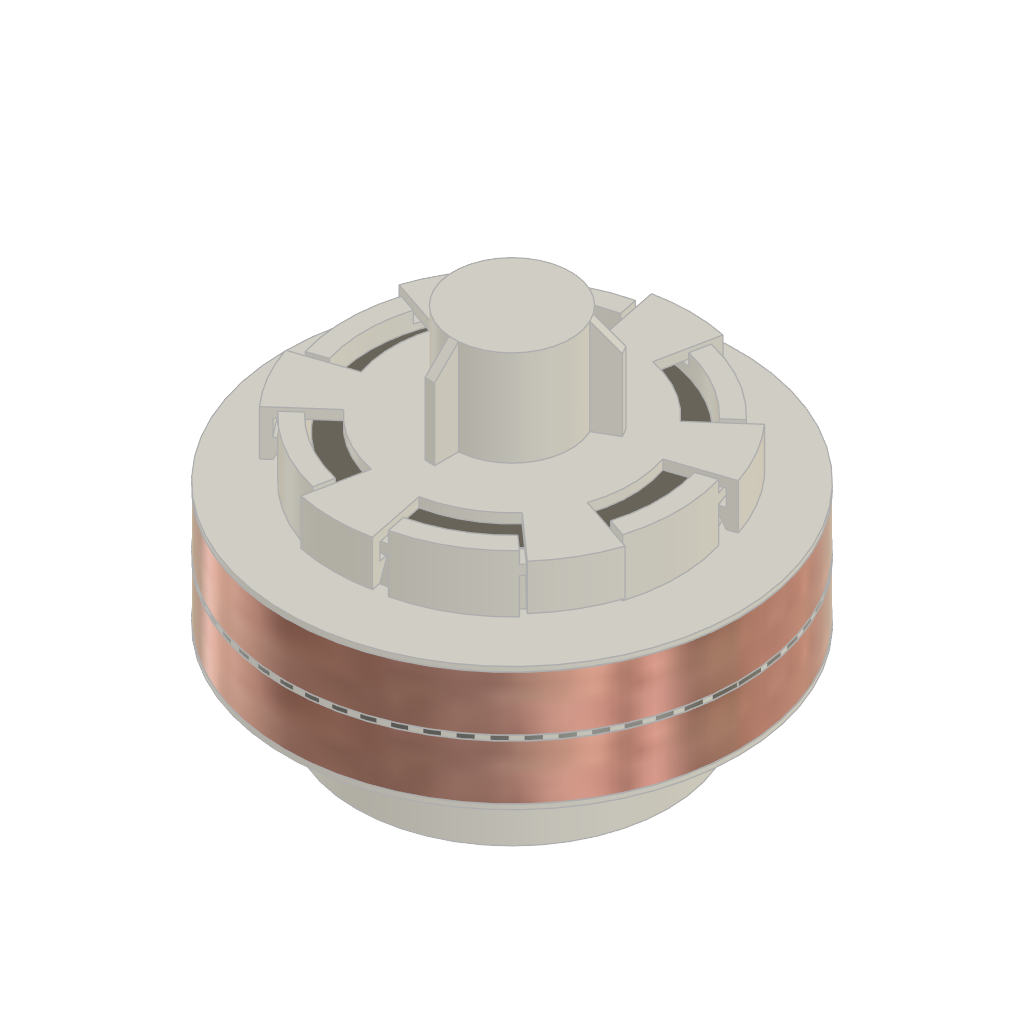
vcm_switch_v01 (Autodesk Fusion 360 design; units mm, degrees)
part number: 2026-10-25-15-28-20-150
part number: 2026-10-28-20-44-21-874
part number: 2026-10-28-20-48-56-404
Autodesk Fusion 360 part; units mm, degrees
sketch "Sketch1" plane through (0, 0, 0) normal (0, 1, 0) x (1, 0, 0)
  line L0 (2, -1.9) -> (2, -2.9)
  line L1 (2, -2.9) -> (5.95, -2.9)
  line L2 (5.95, -2.9) -> (5.95, 0)
  line L3 (5.95, 0) -> (3.9, 0)
  line L4 (1.85, -3.55) -> (1.85, -4.1715)
  line L5 (2.05, -5.1) -> (0.55, -5.1)
  line L6 (0.55, -5.1) -> (0.55, -9.7)
  line L7 (0.55, -9.7) -> (0, -9.7)
  line L8 (0, -9.7) -> (0, -3.25)
  line L9 (3.9, -5.9) -> (2, -4)
  line L10 (2, -4) -> (2, -3)
  line L11 (2, -3) -> (5.95, -3)
  line L12 (5.95, -5.9) -> (3.9, -5.9)
  line L13 (5.95, -3) -> (5.95, -5.9)
  line L14 (0, 0) -> (0, -84.9721) construction
  line L15 (0, 0) -> (-29, 0) construction
  line L16 (12.0457, -8.11) -> (9.5457, -8.11) construction
  line L17 (9.5457, -8.11) -> (9.5457, -9.61) construction
  line L18 (9.5457, -9.61) -> (12.0457, -9.61) construction
  line L19 (12.0457, -9.61) -> (12.0457, -8.11) construction
  line L20 (17.8976, -6.51) -> (-6.3927, -6.51) construction
  line L21 (-6.3927, -6.51) -> (-6.3927, -8.11) construction
  line L22 (-6.3927, -8.11) -> (17.8976, -8.11) construction
  line L23 (17.8976, -8.11) -> (17.8976, -6.51) construction
  line L24 (0, -10.5) -> (2.45, -10.5)
  line L25 (2.45, -10.5) -> (2.45, -6.5)
  line L26 (2.45, -6.5) -> (7.5, -6.5)
  line L27 (7.5, -6.5) -> (7.5, -4.6)
  line L28 (2.05, -6.1) -> (2.05, -10.1)
  line L29 (0, -10.1) -> (0, -10.5)
  line L30 (4.95, 0.1) -> (4.95, 4.5)
  line L31 (4.95, 4.5) -> (2.9, 4.5)
  line L32 (2.9, 4.5) -> (2.9, 0.7)
  line L33 (2.9, 0.7) -> (0, 0.7)
  line L34 (0, -2.65) -> (0, 0.7)
  line L35 (2.05, -6.1) -> (7.1, -6.1)
  line L36 (6.15, -6) -> (6.15, 4.1)
  line L37 (0.9, -10.1) -> (0.9, -5.3)
  line L38 (0.9, -5.3) -> (1.3, -5.3)
  line L39 (1.3, -5.3) -> (1.3, -10.1)
  line L40 (3.6586, -5.9) -> (2.05, -5.9)
  line L41 (2.05, -5.9) -> (2.05, -5.1)
  line L42 (3.6586, -5.8) -> (1.85, -4.1715)
  line L43 (1.85, -2.35) -> (1.55, -2.65)
  line L44 (1.55, -2.65) -> (0, -2.65)
  line L45 (1.85, -3.55) -> (1.55, -3.25)
  line L46 (1.55, -3.25) -> (0, -3.25)
  line L47 (2.05, -10.1) -> (1.3, -10.1)
  line L48 (0.9, -10.1) -> (0, -10.1)
  line L49 (3.8586, 0.1) -> (4.95, 0.1)
  line L50 (3.9, 0) -> (2, -1.9)
  line L51 (6.15, 4.1) -> (5.15, 4.1)
  line L52 (5.15, 4.1) -> (5.15, 4.5)
  line L53 (5.15, 4.5) -> (6.55, 4.5)
  line L54 (1.85, -2.35) -> (1.85, -1.7085)
  line L55 (3.6586, -5.9) -> (3.6586, -5.8)
  line L56 (0, 0) -> (0, 5.1151) construction
  line L57 (0, 5.1151) -> (6.75, 5.1151) construction
  line L58 (6.56, -3.89) -> (9.5, -3.89)
  line L59 (9.5, -3.89) -> (9.5, -1.61)
  line L60 (9.5, -1.61) -> (6.56, -1.61)
  line L61 (6.56, -1.61) -> (6.56, -3.89)
  line L62 (5.95, -3) -> (5.95, -2.9) construction
  line L63 (5.95, -2.95) -> (6.56, -2.95) construction
  line L64 (6.56, -2.75) -> (9.5, -2.75) construction
  line L65 (6.75, 5.1151) -> (7, 1.1229) construction
  line L66 (6.56, 0.89) -> (9.5, 0.89)
  line L67 (9.5, 0.89) -> (9.5, -1.39)
  line L68 (9.5, -1.39) -> (6.56, -1.39)
  line L69 (6.56, -1.39) -> (6.56, 0.89)
  line L70 (6.55, -1.4) -> (9.5, -1.4)
  line L71 (9.5, -1.4) -> (9.5, -1.6)
  line L72 (9.5, -1.6) -> (6.55, -1.6)
  line L73 (6.55, 0.9) -> (9.5, 0.9)
  line L74 (9.5, 0.9) -> (9.5, 1.1)
  line L75 (9.5, 1.1) -> (6.55, 1.1)
  line L76 (6.55, -1.4) -> (6.55, 0.9)
  line L77 (6.55, 1.1) -> (6.55, 4.5)
  line L78 (6.55, -3.9) -> (9.5, -3.9)
  line L79 (9.5, -3.9) -> (9.5, -4.1)
  line L80 (9.5, -4.1) -> (6.55, -4.1)
  line L81 (6.55, -5.6) -> (6.55, -4.1)
  line L82 (6.55, -3.9) -> (6.55, -1.6)
  line L83 (11.8383, 3.9) -> (9.7997, 3.9) construction
  line L84 (9.7997, 3.9) -> (9.7997, 0.4) construction
  line L85 (9.7997, 0.4) -> (11.8383, 0.4) construction
  line L86 (11.8383, 0.4) -> (11.8383, 3.9) construction
  line L87 (11.8383, 0.3) -> (9.7997, 0.3) construction
  line L88 (9.7997, 0.3) -> (9.7997, -3.2) construction
  line L89 (9.7997, -3.2) -> (11.8383, -3.2) construction
  line L90 (11.8383, -3.2) -> (11.8383, 0.3) construction
  line L91 (6.15, -6) -> (6.95, -6)
  line L92 (6.95, -6) -> (6.95, -5.6)
  line L93 (6.95, -5.6) -> (6.55, -5.6)
  line L94 (6.75, -5.4) -> (7.1, -5.4)
  line L95 (7.1, -5.4) -> (7.1, -6.1)
  line L96 (6.75, -5.4) -> (6.75, -5.3)
  line L97 (6.75, -5.3) -> (7.1, -4.6)
  line L98 (7.1, -4.6) -> (7.5, -4.6)
  line L99 (6.55, -1.4) -> (6.55, -1.6)
  line L100 (9.5, -3.89) -> (6.56, -3.89)
  line L101 (6.56, -3.89) -> (6.56, 0.89)
  line L102 (6.56, 0.89) -> (9.5, 0.89)
  line L103 (9.5, 0.89) -> (9.5, -3.89)
  line L104 (1.55, -3.25) -> (1.55, -2.65) construction
  line L105 (2, -3) -> (2, -2.9) construction
  line L106 (1.55, -2.95) -> (2, -2.95) construction
  line L107 (3.8586, 0.1) -> (1.85, -1.7085)
  line L108 (12.2476, -3.1807) -> (13.0108, -3.1807)
  dimension "d1" = 2
  dimension "d3" = 2.9
  dimension "d4" = 5.95
  dimension "d18" = 1.5
  dimension "d19" = 2.5
  dimension "d20" = 1.6
  dimension "d23" = 0.4
  dimension "d26" = 0.01
  dimension "d45" = 0.4
  dimension "d220" = 0.4
  dimension "d221" = 0.2
  dimension "d224" = 2.05
  dimension "d227" = 1.3
  dimension "d228" = 0.4
  dimension "d229" = 0.4
  dimension "d230" = 0.2
  dimension "d231" = 5
  dimension "d235" = 0.2
  dimension "d238" = 0.6
  dimension "d247" = 0.4
  dimension "d253" = 0.35
  dimension "d325" = 0.3
  dimension "d328" = 2.9
  dimension "d329" = 1
  dimension "d331" = 5.95
  dimension "d337" = 0.2
  dimension "d363" = 135
  dimension "d364" = 0.3
  dimension "d365" = 135
  dimension "d367" = 0.15
  dimension "d394" = 6
  dimension "d395" = 0.1
  dimension "d406" = 1
  dimension "d407" = 135
  dimension "d409" = 4
  dimension "d411" = 0.1
  dimension "d413" = 0.2
  dimension "d414" = 0.4
  dimension "d415" = 3.8
  dimension "d416" = 4
  dimension "d417" = 13.5
  dimension "d420" = 0.01
  dimension "d422" = 9.5
  dimension "d423" = 4
  dimension "d424" = 7
  dimension "d425" = 0.2
  dimension "d426" = 0.01
  dimension "d427" = 0.01
  dimension "d429" = 0.01
  dimension "d431" = 0.1
  dimension "d432" = 0.2
  dimension "d433" = 3.5
  dimension "d434" = 0.01
  dimension "d435" = 3.4
  dimension "d436" = 0.4
  dimension "d437" = 2.9
  dimension "d438" = 1
  dimension "d439" = 0.1
  dimension "d440" = 0.1
  dimension "d441" = 0.15
  dimension "d442" = 0.2
  dimension "d443" = 0.8
  dimension "d444" = 0.4
  dimension "d445" = 0.2
  dimension "d446" = 0.2
  dimension "d447" = 0.1
  dimension "d553" = 0.1
  dimension "d554" = 3
  dimension "d557" = 0.5
  dimension "d559" = 0.1
  dimension "d560" = 135
  dimension "d561" = 3
  dimension "d597" = 3.4807
  constraint vertical L0
  constraint perpendicular L0 L1
  constraint perpendicular L1 L2
  constraint perpendicular L2 L3
  constraint parallel L4 L6
  constraint perpendicular L6 L7
  constraint coincident L14.start L15.start
  constraint perpendicular L14 L15
  constraint coincident L14 L8.end
  constraint horizontal L16
  constraint vertical L17
  constraint horizontal L18
  constraint vertical L19
  constraint horizontal L20
  constraint vertical L21
  constraint horizontal L22
  constraint vertical L23
  constraint coincident L14 L24.start
  constraint perpendicular L14 L24
  constraint perpendicular L20 L25
  constraint perpendicular L13 L26
  constraint perpendicular L12 L27
  constraint perpendicular L22 L28
  constraint coincident L14 L29.start
  constraint perpendicular L14 L48
  constraint coincident L16.start L22
  constraint coincident L14.start L3
  constraint perpendicular L30 L31
  constraint coincident L14 L33.end
  constraint perpendicular L14 L33
  constraint perpendicular L28 L35
  constraint coincident L14 L34.start
  constraint perpendicular L35 L36
  constraint perpendicular L4 L5
  constraint perpendicular L20 L37
  constraint perpendicular L37 L38
  constraint perpendicular L39 L47
  constraint collinear L47 L48
  constraint perpendicular L30 L49
  constraint collinear L28 L41
  constraint perpendicular L10 L11
  constraint coincident L34.start L44.end
  constraint coincident L8.end L46.end
  constraint coincident L43.start L54.start
  constraint vertical L43.end L45.end
  constraint equal L43 L45
  constraint collinear L0 L10
  constraint coincident L0.end L1.start
  constraint perpendicular L36 L51
  constraint perpendicular L51 L52
  constraint perpendicular L52 L53
  constraint coincident L53.end L77.end
  constraint perpendicular L40 L55
  constraint collinear L12 L40
  constraint collinear L31 L53
  constraint perpendicular L15 L56
  constraint perpendicular L34 L57
  constraint horizontal L58
  constraint vertical L59
  constraint horizontal L60
  constraint vertical L61
  constraint perpendicular L1 L62
  constraint midpoint L62 L63.start
  constraint coincident L61 L63.end
  constraint perpendicular L61 L63
  constraint midpoint L61 L64.start
  constraint midpoint L59 L64.end
  constraint perpendicular L32 L33
  constraint horizontal L66
  constraint vertical L67
  constraint horizontal L68
  constraint vertical L69
  constraint equal L60 L66
  constraint equal L59 L67
  constraint collinear L59 L67
  constraint perpendicular L70 L76
  constraint perpendicular L70 L71
  constraint perpendicular L72 L82
  constraint collinear L59 L71
  constraint collinear L76 L82
  constraint perpendicular L73 L77
  constraint perpendicular L73 L74
  constraint perpendicular L75 L76
  constraint equal L71 L74
  constraint collinear L71 L74
  constraint collinear L76 L77
  constraint perpendicular L59 L78
  constraint perpendicular L78 L79
  constraint perpendicular L80 L81
  constraint equal L71 L79
  constraint collinear L71 L79
  constraint collinear L81 L82
  constraint horizontal L83
  constraint vertical L84
  constraint horizontal L85
  constraint vertical L86
  constraint horizontal L87
  constraint vertical L88
  constraint horizontal L89
  constraint vertical L90
  constraint collinear L86 L90
  constraint collinear L84 L88
  constraint equal L86 L90
  constraint perpendicular L36 L91
  constraint perpendicular L91 L92
  constraint perpendicular L36 L93
  constraint coincident L81.start L93.end
  constraint perpendicular L59 L94
  constraint perpendicular L94 L96
  constraint parallel L94 L98
  constraint coincident L27.end L98.end
  constraint perpendicular L95 L98
  constraint horizontal L100
  constraint vertical L101
  constraint horizontal L102
  constraint vertical L103
  constraint midpoint L104 L106.start
  constraint midpoint L105 L106.end
  constraint horizontal L106
  constraint horizontal L44
  constraint coincident L95 L97.end
  constraint perpendicular L88 L108
  measures "d1" distance of L0 L14
  measures "d3" distance of L1.end L2.end
  measures "d4" distance of L2 L14
  measures "d18" distance of L16.start L18.end
  measures "d19" distance of L17.end L18.end
  measures "d20" distance of L20.start L22.end
  measures "d23" distance of L24 L47
  measures "d26" distance of L20 L26
  measures "d45" distance of L25 L28
  measures "d220" distance of L26 L35
  measures "d221" distance of L13 L36
  measures "d224" distance of L14 L28
  measures "d227" distance of L14 L39
  measures "d228" distance of L37 L39
  measures "d229" distance of L7 L48
  measures "d230" distance of L5 L38
  measures "d231" distance of L5 L47
  measures "d235" distance of L35 L40
  measures "d238" distance of L44 L46
  measures "d247" distance of L36 L81
  measures "d253" distance of L6 L37
  measures "d328" distance of L11.end L12.start
  measures "d329" distance of L9.end L10.end
  measures "d331" distance of L14.start L13
  measures "d363" angle of L43 L54
  measures "d364" distance of L4 L45.end
  measures "d365" angle of L4 L45
  measures "d367" distance of L0 L54
  measures "d394" distance of L40 L49
  measures "d395" distance of L1 L11
  measures "d406" distance of L0.end L0.start
  measures "d407" angle of L0 L50
  measures "d409" distance of L49 L51
  measures "d411" distance of L40.start L42.start
  measures "d413" distance of L30 L52
  measures "d414" distance of L51.end L52.end
  measures "d415" distance of L31 L33
  measures "d416" distance of L24 L26
  measures "d420" distance of L61 L82
  measures "d422" distance of L14 L59
  measures "d423" distance of L57.end L65.end
  measures "d424" horizontal distance of L14.start L65.end
  measures "d425" distance of L70.end L71.end
  measures "d426" distance of L60 L72
  measures "d427" distance of L68 L70
  measures "d429" distance of L58 L78
  measures "d431" distance of L85 L87
  measures "d432" distance of L51 L83
  measures "d433" distance of L83.start L85.end
  measures "d434" distance of L66 L73
  measures "d435" distance of L53 L75
  measures "d436" distance of L91.end L92.end
  measures "d437" distance of L32 L56
  measures "d438" distance of L36.end L51.end
  measures "d439" distance of L3 L49
  measures "d440" distance of L35 L91
  measures "d441" distance of L92 L95
  measures "d442" distance of L93 L94
  measures "d443" distance of L94 L98
  measures "d444" distance of L27 L95
  measures "d445" distance of L92 L96
  measures "d446" distance of L81 L96
  measures "d447" distance of L94.start L96.end
  measures "d553" distance of L49.start L50
  measures "d554" angle of L50 L107
  measures "d557" distance of L80 L98
  measures "d559" distance of L9 L42.start
  measures "d560" angle of L9 L10
  measures "d561" angle of L9 L42
  measures "d597" distance of L87 L108
revolve "Revolve1" add sketch "Sketch1" angle 360 about axis through (0, 0, 0) along (0, 0, 1) contours L24 L25 L26 L27 L28 L29 L35 L37 L38 L39 L47 L48 L94 L95 L96 L97 L98 makes body 1 in component "Base"
revolve "Revolve1'" add sketch "Sketch1" angle 360 about axis through (0, 0, 2.65) along (0, 0, -1) separate body contours L0 L1 L2 L3 L50 | L9 L10 L11 L12 L13 makes body 2 at (5.9204, 0.5924, 4.9333) makes body 3 at (5.9426, 0.2966, 1.9333) in component "Magnets"
revolve "Revolve1''" add sketch "Sketch1" angle 360 about axis through (0, 0, 2.65) along (0, 0, -1) separate body contours L30 L31 L32 L33 L34 L43 L44 L49 L54 L107 makes body 4 in component "Stem"
sketch "Sketch13" plane through (0, 0, -0.7) normal (0, 0, -1) x (1, 0, 0)
  circle A0 centre (0, 0) radius 2.9
  line L0 (0.47, -1.9) -> (0, -1.9)
  line L1 (0, 0) -> (0, -1.9) construction
  line L2 (0.57, -1.3717) -> (0, -1.3717) construction
  line L3 (0.47, -0.47) -> (0.47, -1.2717)
  line L4 (0.47, -1.4717) -> (0.47, -1.9)
  arc A1 (0.47, -1.4717) -> (0.47, -1.2717) centre (0.47, -1.3717) ccw
  arc A2 (-0.47, -1.2717) -> (-0.47, -1.4717) centre (-0.47, -1.3717) ccw
  line L5 (-0.47, -1.4717) -> (-0.47, -1.9)
  line L6 (-0.47, -1.9) -> (0, -1.9)
  line L7 (-0.47, -0.47) -> (-0.47, -1.2717)
  arc A3 (1.4717, 0.47) -> (1.2717, 0.47) centre (1.3717, 0.47) ccw
  line L8 (1.4717, 0.47) -> (1.9, 0.47)
  line L9 (1.9, 0.47) -> (1.9, 0)
  line L10 (0.47, 0.47) -> (1.2717, 0.47)
  arc A4 (1.2717, -0.47) -> (1.4717, -0.47) centre (1.3717, -0.47) ccw
  line L11 (1.4717, -0.47) -> (1.9, -0.47)
  line L12 (1.9, -0.47) -> (1.9, 0)
  line L13 (0.47, -0.47) -> (1.2717, -0.47)
  arc A5 (-0.47, 1.4717) -> (-0.47, 1.2717) centre (-0.47, 1.3717) ccw
  line L14 (-0.47, 1.4717) -> (-0.47, 1.9)
  line L15 (-0.47, 1.9) -> (0, 1.9)
  line L16 (-0.47, 0.47) -> (-0.47, 1.2717)
  arc A6 (0.47, 1.2717) -> (0.47, 1.4717) centre (0.47, 1.3717) ccw
  line L17 (0.47, 1.4717) -> (0.47, 1.9)
  line L18 (0.47, 1.9) -> (0, 1.9)
  line L19 (0.47, 0.47) -> (0.47, 1.2717)
  arc A7 (-1.4717, -0.47) -> (-1.2717, -0.47) centre (-1.3717, -0.47) ccw
  line L20 (-1.4717, -0.47) -> (-1.9, -0.47)
  line L21 (-1.9, -0.47) -> (-1.9, 0)
  line L22 (-0.47, -0.47) -> (-1.2717, -0.47)
  arc A8 (-1.2717, 0.47) -> (-1.4717, 0.47) centre (-1.3717, 0.47) ccw
  line L23 (-1.4717, 0.47) -> (-1.9, 0.47)
  line L24 (-1.9, 0.47) -> (-1.9, 0)
  line L25 (-0.47, 0.47) -> (-1.2717, 0.47)
  dimension "d343" = 1.9
  dimension "d344" = 0.2
  dimension "d345" = 0.57
  dimension "d347" = 360
  constraint vertical L3
  constraint coincident A0.centre L1.start
  constraint vertical L1
  constraint coincident L2.start A1
  constraint coincident L1 L2.end
  constraint perpendicular L1 L2
  constraint collinear L3 L4
  constraint coincident A1.centre L3
  constraint coincident A1.centre L2
  constraint perpendicular L0 L4
  constraint symmetric L3.start L1 L7.start
  constraint symmetric L0.start L1 L5.end
  constraint symmetric L0.end L1 L6.end
  constraint symmetric L1 L3.end A2.start
  constraint symmetric L1 L4.start A2.end
  constraint symmetric L1 A1 A2
  constraint coincident L3.start L13.start
  measures "d343" distance of L0 A0.centre
  measures "d344" diameter of A1
  measures "d345" distance of L2.start L2.end
extrude "Extrude1" add sketch "Sketch13" along normal blind 3.8 contours L0 L3 L4 A1 A2 L5 L6 L7 A3 L8 L9 L10 A4 L11 L12 L13 A5 L14 L15 L16 A6 L17 L18 L19 A7 L20 L21 L22 A8 L23 L24 L25 bodies 4 in component "Stem"
revolve "Revolve1'''" add sketch "Sketch1" angle 360 about axis through (0, 0, 2.65) along (0, 0, -1) separate body contours L36 L51 L52 L53 L73 L74 L75 L76 L77 L78 L79 L80 L81 L82 L91 L92 L93 L99 | L70 L72 L99 L101 | L70 L71 L72 L101 L103 makes body 5 in component "Bobbin"
revolve "Revolve1''''" add sketch "Sketch1" angle 360 about axis through (0, 0, 9.7) along (0, 0, -1) separate body contours L4 L5 L6 L7 L8 L40 L41 L42 L45 L46 L55 makes body 6 in component "Core Bottom"
revolve "Revolve1'''''" add sketch "Sketch1" angle 360 about axis through (0, 0, 0) along (0, 0, 1) separate body contours L70 L72 L99 L101 | L70 L71 L72 L101 L103 | L58 L59 L60 L61 L100 L101 L103 | L66 L67 L68 L69 L101 L102 L103 makes body 7 at (8.4846, -0.472, 1.39) makes body 8 at (8.4569, -0.7974, 1.4) makes body 9 at (8.4602, -0.7979, 1.61) in component "Coil"
sketch "Sketch24" plane through (0, 0, 6.5) normal (0, 0, 1) x (-1, 0, 0)
  circle A0 centre (0, 0) radius 7.5
  circle A1 centre (0, 0) radius 2.45
  line L0 (0, 0) -> (3.4644, 0) construction
  line L1 (0, 0) -> (0, 7.5) construction
  line L2 (-1.5, 7.3485) -> (-1, 4.899)
  line L3 (1.5, 7.3485) -> (1, 4.899)
  circle A2 centre (0, 0) radius 5
  line L4 (-1, 4.899) -> (0, 0) construction
  line L5 (1, 4.899) -> (0, 0) construction
  line L6 (-1.5, 7.3485) -> (1.5, 7.3485) construction
  line L7 (-7.114, 2.3752) -> (-4.7426, 1.5835)
  line L8 (-5.614, 4.9733) -> (-3.7426, 3.3155)
  line L9 (-5.614, -4.9733) -> (-3.7426, -3.3155)
  line L10 (-7.114, -2.3752) -> (-4.7426, -1.5835)
  line L11 (1.5, -7.3485) -> (1, -4.899)
  line L12 (-1.5, -7.3485) -> (-1, -4.899)
  line L13 (7.114, -2.3752) -> (4.7426, -1.5835)
  line L14 (5.614, -4.9733) -> (3.7426, -3.3155)
  line L15 (5.614, 4.9733) -> (3.7426, 3.3155)
  line L16 (7.114, 2.3752) -> (4.7426, 1.5835)
  dimension "d449" = 10
  dimension "d451" = 3
  dimension "d453" = 360
  constraint coincident A0.centre A1.centre
  constraint horizontal L0
  constraint perpendicular L0 L1
  constraint coincident A0 L2.start
  constraint coincident A0 L3.start
  constraint coincident A0 L1.end
  constraint coincident L2.end A2
  constraint coincident L3.end A2
  constraint parallel L3 L5
  constraint parallel L2 L4
  constraint horizontal L6
  measures "d449" diameter of A2
  measures "d451" distance of L2.start L3.start
extrude "Extrude2" cut sketch "Sketch24" against normal up to surface (1.9 mm away) contours A0 A2 L13 L16 | A0 L3 A2 L15 | A0 A2 L11 L14 | A0 L2 A2 L8 | A0 A2 L9 L12 | A0 A2 L7 L10 bodies 1 in component "Base"
sketch "Sketch25" plane through (0, 0, 6) normal (0, 0, 1) x (-1, 0, 0)
  circle A0 centre (0, 0) radius 6.95
  circle A1 centre (0, 0) radius 6.15
  line L0 (7.114, -2.3752) -> (4.7426, -1.5835)
  arc A2 (5.614, -4.9733) -> (7.114, -2.3752) centre (0, 0) ccw
  line L1 (4.7426, 1.5835) -> (7.114, 2.3752)
  line L2 (5.614, 4.9733) -> (3.7426, 3.3155)
  line L3 (1, 4.899) -> (1.5, 7.3485)
  arc A3 (3.7426, 3.3155) -> (1, 4.899) centre (0, 0) ccw
  line L4 (-1.5, 7.3485) -> (-1, 4.899)
  line L5 (-3.7426, 3.3155) -> (-5.614, 4.9733)
  line L6 (-7.114, 2.3752) -> (-4.7426, 1.5835)
  line L7 (-4.7426, -1.5835) -> (-7.114, -2.3752)
  arc A4 (-4.7426, 1.5835) -> (-4.7426, -1.5835) centre (0, 0) ccw
  line L8 (-5.614, -4.9733) -> (-3.7426, -3.3155)
  line L9 (-1, -4.899) -> (-1.5, -7.3485)
  line L10 (1.5, -7.3485) -> (1, -4.899)
  line L11 (3.7426, -3.3155) -> (5.614, -4.9733)
  arc A5 (1, -4.899) -> (3.7426, -3.3155) centre (0, 0) ccw
  circle A6 centre (0, 0) radius 2.45
  circle A7 centre (0, 0) radius 5
  line L12 (-1.1952, 4.8551) -> (-1.5854, 6.7668)
  line L13 (1.5854, 6.7668) -> (1.1952, 4.8551)
  line L14 (-4.8022, 1.3925) -> (-6.6529, 2.0104)
  line L15 (-5.0675, 4.7564) -> (-3.607, 3.4626)
  line L16 (-3.607, -3.4626) -> (-5.0675, -4.7564)
  line L17 (-6.6529, -2.0104) -> (-4.8022, -1.3925)
  line L18 (1.1952, -4.8551) -> (1.5854, -6.7668)
  line L19 (-1.5854, -6.7668) -> (-1.1952, -4.8551)
  line L20 (4.8022, -1.3925) -> (6.6529, -2.0104)
  line L21 (5.0675, -4.7564) -> (3.607, -3.4626)
  line L22 (3.607, 3.4626) -> (5.0675, 4.7564)
  line L23 (6.6529, 2.0104) -> (4.8022, 1.3925)
  arc A8 (4.7426, -1.5835) -> (4.7426, 1.5835) centre (0, 0) ccw
  arc A9 (7.114, 2.3752) -> (5.614, 4.9733) centre (0, 0) ccw
  arc A10 (1.5, 7.3485) -> (-1.5, 7.3485) centre (0, 0) ccw
  arc A11 (-1, 4.899) -> (-3.7426, 3.3155) centre (0, 0) ccw
  arc A12 (-5.614, 4.9733) -> (-7.114, 2.3752) centre (0, 0) ccw
  arc A13 (-7.114, -2.3752) -> (-5.614, -4.9733) centre (0, 0) ccw
  arc A14 (-3.7426, -3.3155) -> (-1, -4.899) centre (0, 0) ccw
  arc A15 (-1.5, -7.3485) -> (1.5, -7.3485) centre (0, 0) ccw
  dimension "d456" = 0.2
  dimension "d458" = 0.2
  dimension "d460" = 360
  constraint concentric A2 A7
  constraint coincident L5.start A7
  constraint coincident A7 L12.start
  constraint coincident A7 L13.end
  constraint parallel L4 L12
  constraint parallel L3 L13
  constraint coincident A0 L13.start
  constraint coincident A0 L12.end
  measures "d456" distance of L4 L12
  measures "d458" distance of L3 L13
extrude "Extrude7" add sketch "Sketch25" along normal up to surface (0.5 mm away) and the other way up to surface (1.9 mm away) contours A0 A1 L20 L23 | A0 A1 L13 L22 | A0 A1 L18 L21 | A0 A1 L12 L15 | A0 A1 L16 L19 | A0 A1 L14 L17 bodies 5 in component "Bobbin"
sketch "Sketch27" plane through (0, 0, -4.5) normal (0, 0, -1) x (1, 0, 0)
  circle A0 centre (0, 0) radius 5.15
  circle A1 centre (0, 0) radius 6.55
  line L0 (5.15, 2.9734) -> (0, 5.9467)
  line L1 (0, 5.9467) -> (-5.15, 2.9734)
  line L2 (-5.15, 2.9734) -> (-5.15, -2.9734)
  line L3 (-5.15, -2.9734) -> (0, -5.9467)
  line L4 (0, -5.9467) -> (5.15, -2.9734)
  line L5 (5.15, -2.9734) -> (5.15, 2.9734)
  constraint coincident A0.centre A1.centre
  constraint vertical L2
  constraint tangent A0 L2
extrude "Extrude6" cut sketch "Sketch27" against normal up to surface (0.4 mm away) contours A0 L4 L5 | A0 L0 L5 | A0 L0 L1 | A0 L3 L4 | A0 L1 L2 | A0 L2 L3 bodies 5 in component "Bobbin"
sketch "Sketch28" plane through (0, 0, -4.5) normal (0, 0, -1) x (1, 0, 0)
  circle A0 centre (0, 0) radius 2.9
  circle A1 centre (0, 0) radius 4.95
  line L0 (0, 5.9467) -> (5.15, 2.9734)
  line L1 (5.15, 2.9734) -> (5.15, -2.9734)
  line L2 (5.15, -2.9734) -> (0, -5.9467)
  line L3 (0, -5.9467) -> (-5.15, -2.9734)
  line L4 (-5.15, -2.9734) -> (-5.15, 2.9734)
  line L5 (-5.15, 2.9734) -> (0, 5.9467)
  circle A2 centre (0, 0) radius 6.55
  line L6 (-5.05, -2.9156) -> (-5.05, 2.9156)
  line L7 (-5.05, 2.9156) -> (0, 5.8312)
  line L8 (0, 5.8312) -> (5.05, 2.9156)
  line L9 (5.05, 2.9156) -> (5.05, -2.9156)
  line L10 (5.05, -2.9156) -> (0, -5.8312)
  line L11 (0, -5.8312) -> (-5.05, -2.9156)
  dimension "d467" = 0.1
extrude "Extrude5" add sketch "Sketch28" against normal up to surface (4.4 mm away) contours L6 L7 L8 L9 L10 L11 bodies 4 in component "Stem"
sketch "Sketch34" plane through (0, 0, 6.5) normal (0, 0, 1) x (-1, 0, 0)
  circle A0 centre (0, 0) radius 2.45
  line L0 (1.5, -7.3485) -> (1, -4.899)
  arc A1 (1, -4.899) -> (3.7426, -3.3155) centre (0, 0) ccw
  line L1 (3.7426, -3.3155) -> (5.614, -4.9733)
  arc A2 (5.614, -4.9733) -> (7.114, -2.3752) centre (0, 0) ccw
  line L2 (7.114, -2.3752) -> (4.7426, -1.5835)
  arc A3 (4.7426, -1.5835) -> (4.7426, 1.5835) centre (0, 0) ccw
  line L3 (4.7426, 1.5835) -> (7.114, 2.3752)
  arc A4 (7.114, 2.3752) -> (5.614, 4.9733) centre (0, 0) ccw
  line L4 (5.614, 4.9733) -> (3.7426, 3.3155)
  arc A5 (3.7426, 3.3155) -> (1, 4.899) centre (0, 0) ccw
  line L5 (1, 4.899) -> (1.5, 7.3485)
  arc A6 (1.5, 7.3485) -> (-1.5, 7.3485) centre (0, 0) ccw
  line L6 (-1.5, 7.3485) -> (-1, 4.899)
  arc A7 (-1, 4.899) -> (-3.7426, 3.3155) centre (0, 0) ccw
  line L7 (-3.7426, 3.3155) -> (-5.614, 4.9733)
  arc A8 (-5.614, 4.9733) -> (-7.114, 2.3752) centre (0, 0) ccw
  line L8 (-7.114, 2.3752) -> (-4.7426, 1.5835)
  arc A9 (-4.7426, 1.5835) -> (-4.7426, -1.5835) centre (0, 0) ccw
  line L9 (-4.7426, -1.5835) -> (-7.114, -2.3752)
  arc A10 (-7.114, -2.3752) -> (-5.614, -4.9733) centre (0, 0) ccw
  line L10 (-5.614, -4.9733) -> (-3.7426, -3.3155)
  arc A11 (-3.7426, -3.3155) -> (-1, -4.899) centre (0, 0) ccw
  line L11 (-1, -4.899) -> (-1.5, -7.3485)
  arc A12 (-1.5, -7.3485) -> (1.5, -7.3485) centre (0, 0) ccw
  line L12 (0, 0) -> (0, 3.4418) construction
  line L13 (-0.2, 2.4418) -> (-0.2, 3.4418)
  line L14 (-0.2, 3.4418) -> (0.2, 3.4418)
  line L15 (0.2, 3.4418) -> (0.2, 2.4418)
  line L16 (-2.0147, -1.3941) -> (-2.8807, -1.8941)
  line L17 (-2.8807, -1.8941) -> (-3.0807, -1.5477)
  line L18 (-3.0807, -1.5477) -> (-2.2147, -1.0477)
  line L19 (2.2147, -1.0477) -> (3.0807, -1.5477)
  line L20 (3.0807, -1.5477) -> (2.8807, -1.8941)
  line L21 (2.8807, -1.8941) -> (2.0147, -1.3941)
  dimension "d570" = 0.4
  dimension "d572" = 360
  dimension "d576" = 1
  constraint coincident A0.centre A1.centre
  constraint vertical L12
  constraint coincident A0 L13.start
  constraint parallel L12 L13
  constraint perpendicular L13 L14
  constraint coincident A0 L15.end
  constraint perpendicular L14 L15
  constraint coincident L12.end L14
  constraint midpoint L12.end L14
  measures "d570" distance of L13 L15
  measures "d576" distance of L14.end L15.end
extrude "Extrude3" add sketch "Sketch34" along normal up to surface (4 mm away) contours A0 L13 L14 L15 | A0 L19 L20 L21 | A0 L16 L17 L18 bodies 1 in component "Base"
chamfer "Chamfer1" distance 1 angle 45 3 edges at (2.9807, 1.7209, 10.5) (0, -3.4418, 10.5) (-2.9807, 1.7209, 10.5) tangent chain off on bodies 1 in component "Base"
sketch "Sketch31" plane through (0, 0, 0) normal (1, 0, 0) x (0, 1, 0)
  line L0 (6.15, -4.5) -> (6.15, 6)
  line L1 (6.15, 6) -> (0.85, 6)
  line L2 (0.85, 6) -> (0.85, 10.2)
  line L3 (0.85, 10.2) -> (0, 10.2)
  line L4 (0, 10.2) -> (0, 11.2)
  line L5 (0, 11.2) -> (8.15, 11.2)
  line L6 (8.15, 11.2) -> (8.15, -4.5)
  line L7 (0, 0) -> (0, 14.9785) construction
  line L8 (5.95, 3) -> (-5.95, 3) construction
  line L9 (-5.95, 3) -> (-5.95, 5.9) construction
  line L10 (5.95, 5.9) -> (-5.95, 5.9) construction
  line L11 (5.95, 3) -> (5.95, 5.9) construction
  line L12 (5.95, 0) -> (-5.95, 0) construction
  line L13 (-5.95, 0) -> (-5.95, 2.9) construction
  line L14 (5.95, 2.9) -> (-5.95, 2.9) construction
  line L15 (5.95, 0) -> (5.95, 2.9) construction
  line L16 (2.9156, -4.5) -> (-2.9156, -4.5) construction
  line L17 (-2.9156, -4.5) -> (-5.8312, -4.5) construction
  line L18 (-5.8312, -4.5) -> (-5.8312, -0.1) construction
  line L19 (-5.8312, -0.1) -> (-3.8586, -0.1) construction
  line L20 (-1.85, 1.7085) -> (-1.85, 2.35) construction
  line L21 (-1.55, 2.65) -> (-1.85, 2.35) construction
  line L22 (1.55, 2.65) -> (-1.55, 2.65) construction
  line L23 (1.55, 2.65) -> (1.85, 2.35) construction
  line L24 (1.85, 1.7085) -> (1.85, 2.35) construction
  line L25 (3.8586, -0.1) -> (5.8312, -0.1) construction
  line L26 (5.8312, -4.5) -> (5.8312, -0.1) construction
  line L27 (5.8312, -4.5) -> (2.9156, -4.5) construction
  line L28 (8.15, -4.5) -> (6.15, -4.5)
  line L29 (-1.85, 1.7085) -> (-3.8586, -0.1)
  line L30 (1.85, 1.7085) -> (3.8586, -0.1)
  line L31 (0.55, 9.7) -> (-0.55, 9.7)
  line L32 (-0.55, 5.9) -> (-0.55, 9.7)
  line L33 (-0.55, 5.9) -> (-3.6586, 5.9)
  line L34 (-3.6586, 5.8) -> (-3.6586, 5.9)
  line L35 (-1.85, 4.1715) -> (-3.6586, 5.8)
  line L36 (-1.85, 3.55) -> (-1.85, 4.1715)
  line L37 (-1.55, 3.25) -> (-1.85, 3.55)
  line L38 (1.55, 3.25) -> (-1.55, 3.25)
  line L39 (1.55, 3.25) -> (1.85, 3.55)
  line L40 (1.85, 3.55) -> (1.85, 4.1715)
  line L41 (1.85, 4.1715) -> (3.6586, 5.8)
  line L42 (3.6586, 5.8) -> (3.6586, 5.9)
  line L43 (3.6586, 5.9) -> (0.55, 5.9)
  line L44 (0.55, 5.9) -> (0.55, 9.7)
  line L45 (6.15, 6) -> (3.6586, 6)
  line L46 (3.6586, 6) -> (3.6586, 6.5)
  line L47 (3.6586, 6.5) -> (6.15, 6.5)
  line L48 (6.15, 6.5) -> (6.15, 6)
  dimension "d541" = 2
  dimension "d542" = 1
  dimension "d544" = 0.1
  dimension "d545" = 0.2
  dimension "d577" = 0.3
  dimension "d578" = 0.5
  dimension "d591" = 0.5
  constraint perpendicular L0 L1
  constraint perpendicular L1 L2
  constraint perpendicular L2 L3
  constraint perpendicular L3 L4
  constraint perpendicular L4 L5
  constraint perpendicular L5 L6
  constraint coincident L7.start origin
  constraint parallel L6 L7
  constraint collinear L4 L7
  constraint coincident L0.start L28.end
  constraint coincident L6.end L28.start
  constraint perpendicular L6 L28
  constraint collinear L16 L28
  constraint horizontal L45
  constraint vertical L46
  constraint horizontal L47
  constraint vertical L48
  constraint collinear L42 L46
  measures "d541" distance of L0 L6
  measures "d542" distance of L3 L5
  measures "d544" distance of L1 L10
  measures "d545" distance of L0 L11
  measures "d577" distance of L2 L44
  measures "d578" distance of L3 L31
  measures "d591" distance of L45.end L46.end
revolve "Revolve1''''''" add sketch "Sketch31" angle 360 about axis through (0, 0, 0) along (0, 0, 1) separate body contours L0 L1 L2 L3 L4 L5 L6 L28 L46 L47 L48 makes body 10 in component "Component"
sketch "Sketch37" plane through (0, 0, 0) normal (0, 0, 1) x (1, 0, 0)
  circle A0 centre (0, 0) radius 8.15
  line L0 (-5.05, 2.9156) -> (-5.05, -2.9156) construction
  line L1 (-5.05, -2.9156) -> (0, -5.8312) construction
  line L2 (0, -5.8312) -> (5.05, -2.9156) construction
  line L3 (5.05, -2.9156) -> (5.05, 2.9156) construction
  line L4 (5.05, 2.9156) -> (0, 5.8312) construction
  line L5 (0, 5.8312) -> (-5.05, 2.9156) construction
  line L6 (-5.25, 3.0311) -> (-5.25, -3.0311)
  line L7 (-5.25, -3.0311) -> (0, -6.0622)
  line L8 (0, -6.0622) -> (5.25, -3.0311)
  line L9 (5.25, -3.0311) -> (5.25, 3.0311)
  line L10 (5.25, 3.0311) -> (0, 6.0622)
  line L11 (0, 6.0622) -> (-5.25, 3.0311)
  circle A1 centre (0, 0) radius 6.15
  line L12 (0, 0) -> (0, 9.0559) construction
  line L13 (0.1325, 8.1489) -> (0.1, 6.1492)
  line L14 (0.1, 6.1492) -> (0, 0) construction
  line L15 (-0.1325, 8.1489) -> (-0.1, 6.1492)
  line L16 (-6.9909, 4.1892) -> (-5.2754, 3.1612)
  line L17 (-7.1234, 3.9597) -> (-5.3754, 2.988)
  line L18 (-7.1234, -3.9597) -> (-5.3754, -2.988)
  line L19 (-6.9909, -4.1892) -> (-5.2754, -3.1612)
  line L20 (-0.1325, -8.1489) -> (-0.1, -6.1492)
  line L21 (0.1325, -8.1489) -> (0.1, -6.1492)
  line L22 (6.9909, -4.1892) -> (5.2754, -3.1612)
  line L23 (7.1234, -3.9597) -> (5.3754, -2.988)
  line L24 (7.1234, 3.9597) -> (5.3754, 2.988)
  line L25 (6.9909, 4.1892) -> (5.2754, 3.1612)
  dimension "d581" = 0.2
  dimension "d592" = 0.1
  dimension "d594" = 360
  constraint coincident A0.centre A1.centre
  constraint vertical L12
  constraint coincident A0 L13.start
  constraint coincident A1 L13.end
  constraint parallel L13 L14
  constraint symmetric L12 L13.start L15.start
  constraint symmetric L12 L13.end L15.end
  measures "d592" distance of L12 L13.end
extrude "Extrude1'" add sketch "Sketch37" against normal up to surface (5 mm away) from surface at -0.5 separate body contours A1 makes body 11 in component "Component'"
extrude "Extrude2'" add sketch "Sketch37" along normal blind 1 from surface at -5.5 contours L6 L7 L8 L9 L10 L11 bodies 11 in component "Component'"
extrude "Extrude3'" add sketch "Sketch37" along normal up to surface (11.4 mm away) from surface at -5.5 contours A0 A1 L23 L24 | A0 A1 L15 L16 | A0 A1 L19 L20 bodies 11 in component "Component'"
extrude "Extrude1''" cut sketch "Sketch37" along normal through all from surface at -4.5 contours A0 A1 L23 L24 | A0 A1 L24 L25 | A0 A1 L22 L23 | A0 A1 L13 L15 | A0 A1 L20 L21 | A0 A1 L15 L16 | A0 A1 L19 L20 | A0 A1 L16 L17 | A0 A1 L18 L19 bodies 10 in component "Component"
component "Base" placed x (1, 0, 0) y (0, 1, 0) z (0, 0, 1) at (0, 0, 0)
component "Magnets" placed x (1, 0, 0) y (0, 1, 0) z (0, 0, 1) at (0, 0, 0)
component "Stem" placed x (1, 0, 0) y (0, 1, 0) z (0, 0, 1) at (0, 0, 0)
component "Bobbin" placed x (1, 0, 0) y (0, 1, 0) z (0, 0, 1) at (0, 0, 0)
component "Core Bottom" placed x (1, 0, 0) y (0, 1, 0) z (0, 0, 1) at (0, 0, 0)
component "Coil" placed x (1, 0, 0) y (0, 1, 0) z (0, 0, 1) at (0, 0, 0)
component "Component" placed x (1, 0, 0) y (0, 1, 0) z (0, 0, 1) at (0, 0, 0)
component "Component'" placed x (1, 0, 0) y (0, 1, 0) z (0, 0, 1) at (0, 0, 0)
equation "d3 = d328"
equation "d4 = d331"
equation "d23 = d45"
equation "d220 = d45"
equation "d224 = ( 4.1 / 2 ) * 1 mm"
equation "d227 = ( 2.6 / 2 ) * 1 mm"
equation "d365 = d363"
equation "d422 = ( 19 / 2 ) * 1 mm"
equation "d424 = ( 14 / 2 ) * 1 mm"
equation "d456 = d458"
equation "d561 = d554"
